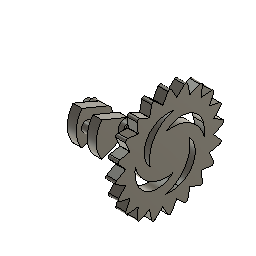
shaft (Autodesk Fusion 360 design; units mm, degrees)
part number: 2026-03-27-15-48-30-231
Autodesk Fusion 360 part; units mm, degrees
sketch "Sketch1" plane through (0, 0, 0) normal (1, 0, 0) x (0, 1, 0)
  circle A0 centre (0, 0) radius 2.5 construction
  circle A1 centre (0, 0) radius 14.5
  circle A2 centre (0, 0) radius 9.5 construction
  circle A3 centre (-9.4991, -0.128) radius 2.5
  circle A4 centre (0, 0) radius 3.5
  line L0 (1.3394, 3.2336) -> (-11.6607, 8.6184)
  line L1 (1.3394, -3.2336) -> (-11.6607, -8.6184)
  line L2 (0, 0) -> (-7.0024, 0) construction
  dimension "d1" = 29
  dimension "d2" = 5
  dimension "d3" = 5
  dimension "d4" = 5
  dimension "d5" = 7
  dimension "d6" = 45
  dimension "d7" = 22.5
  constraint coincident A0.centre A1.centre
  constraint coincident A2 A3.centre
  constraint concentric A2 A4
  constraint coincident A4 L0.start
  constraint coincident A1 L0.end
  constraint coincident A4 L1.start
  constraint coincident A1 L1.end
  constraint tangent A4 L0
  constraint tangent A4 L1
  constraint coincident A3 L2.end
  constraint horizontal L2
  measures "d1" diameter of A1
  measures "d2" diameter of A0
  measures "d3" distance of A1 A2
  measures "d4" diameter of A3
  measures "d5" diameter of A4
  measures "d6" angle of L0 L1
  measures "d7" angle of L1 L2
extrude "Extrude1" add sketch "Sketch1" along normal blind 4.5 contours A1 A4 L0 L1 | A4 picked at (-7.3196, 4.4977)
sketch "Sketch2" plane through (0, 0, 0) normal (-1, 0, 0) x (0, -1, 0)
  circle A0 centre (9.4991, -0.128) radius 2.5
  line L0 (11.6607, 8.6184) -> (-1.3394, 3.2336)
  arc A1 (-1.3394, 3.2336) -> (-1.3394, -3.2336) centre (0, 0) ccw
  line L1 (-1.3394, -3.2336) -> (11.6607, -8.6184)
  arc A2 (11.6607, -8.6184) -> (11.6607, 8.6184) centre (0, 0) ccw
extrude "Extrude2" add sketch "Sketch2" against normal blind 10 contours A0
sketch "Sketch3" plane through (10, 0, 0) normal (1, 0, 0) x (0, 1, 0)
  circle A0 centre (-9.4991, -0.128) radius 2.5
  line L0 (1.3394, 3.2336) -> (-11.6607, 8.6184)
  circle A1 centre (-9.4991, -0.128) radius 2.5
  line L1 (1.3394, 3.2336) -> (-11.6607, 8.6184)
  arc A2 (-11.6607, 8.6184) -> (-11.6607, -8.6184) centre (0, 0) ccw
  line L2 (-11.6607, -8.6184) -> (1.3394, -3.2336)
  arc A3 (1.3394, -3.2336) -> (1.3394, 3.2336) centre (0, 0) ccw
extrude "Extrude3" add sketch "Sketch3" along normal blind 4.5 contours A0 A1 | L0 L1 A2 L2 A3
sketch "Sketch4" plane through (14.5, 0, 0) normal (1, 0, 0) x (0, 1, 0)
  arc A0 (1.3394, -3.2336) -> (1.3394, 3.2336) centre (0, 0) ccw
  line L0 (1.3394, 3.2336) -> (-11.6607, 8.6184)
  arc A1 (-11.6607, 8.6184) -> (-11.6607, -8.6184) centre (0, 0) ccw
  line L1 (-11.6607, -8.6184) -> (1.3394, -3.2336)
  circle A2 centre (0, 0) radius 3.5
  dimension "d14" = 7
  constraint coincident A0.centre A1.centre
  measures "d14" diameter of A2
extrude "Extrude4" add sketch "Sketch4" along normal blind 2.5 contours A0 A2
sketch "Sketch5" plane through (17, 0, 0) normal (1, 0, 0) x (0, 1, 0)
  circle A0 centre (0, 0) radius 3.5
  circle A1 centre (0, 0) radius 2.5
  dimension "d17" = 5
  constraint concentric A0 A1
  measures "d17" diameter of A1
extrude "Extrude5" add sketch "Sketch5" along normal blind 15 contours A1
sketch "Sketch6" plane through (0, 0, 0) normal (-1, 0, 0) x (0, -1, 0)
  line L0 (11.6607, 8.6184) -> (-1.3394, 3.2336)
  arc A0 (-1.3394, 3.2336) -> (-1.3394, -3.2336) centre (0, 0) ccw
  line L1 (-1.3394, -3.2336) -> (11.6607, -8.6184)
  arc A1 (11.6607, -8.6184) -> (11.6607, 8.6184) centre (0, 0) ccw
  circle A2 centre (0, 0) radius 3.5
  constraint coincident A0.centre A1.centre
extrude "Extrude6" add sketch "Sketch6" along normal blind 2.5 contours A0 A2
sketch "Sketch7" plane through (-2.5, 0, 0) normal (-1, 0, 0) x (0, -1, 0)
  circle A0 centre (0, 0) radius 3.5
  circle A1 centre (0, 0) radius 2.5
  dimension "d22" = 5
  constraint concentric A0 A1
  measures "d22" diameter of A1
extrude "Extrude7" add sketch "Sketch7" along normal blind 2.5 contours A1
sketch "Sketch8" plane through (32, 0, 0) normal (1, 0, 0) x (0, 1, 0)
  circle A0 centre (0, 0) radius 2.5
  circle A1 centre (0, 0) radius 2.5
  circle A2 centre (0, 0) radius 22.5
  dimension "d25" = 20
  dimension "d26" = 5
  constraint concentric A0 A1
  constraint concentric A1 A2
  measures "d25" distance of A1 A2
  measures "d26" diameter of A1
extrude "Extrude8" add sketch "Sketch8" along normal blind 5 contours A0 A1 | A2
sketch "Sketch9" plane through (37, 0, 0) normal (1, 0, 0) x (0, 1, 0)
  circle A0 centre (0, 0) radius 22.5
  line L0 (-3.4641, -22.2317) -> (0, -28.2317)
  line L1 (0, -28.2317) -> (3.4641, -22.2317)
  line L2 (3.4641, -22.2317) -> (-3.4641, -22.2317)
  point P0 (0, -24.2317)
  dimension "d29" = 2
  constraint coincident A0 L1.end
  constraint horizontal L2
  constraint coincident A0 L0.start
  measures "d29" distance of P0 L2
extrude "Extrude9" add sketch "Sketch9" against normal up to surface (5 mm away) contours A0 L0 L1
fillet "Fillet1" radius 1 1 edges at (34.5, 0, -28.2317)
pattern_circular "C-Pattern2" count 20 over 360 about axis through (1.75, 0, 0) along (1, 0, 0) of "Extrude9", "Fillet1"
sketch "Sketch10" plane through (37, 0, 0) normal (1, 0, 0) x (0, 1, 0)
  arc A0 (-9.0842, -25.1558) -> (-7.4369, -25.691) centre (-8.1061, -24.9479) ccw
  line L0 (-7.4369, -25.691) -> (-3.5754, -22.2141)
  arc A1 (-3.5754, -22.2141) -> (-3.4641, -22.2317) centre (0, 0) ccw
  line L1 (-3.4641, -22.2317) -> (-0.866, -26.7317)
  arc A2 (-0.866, -26.7317) -> (0.866, -26.7317) centre (0, -26.2317) ccw
  line L2 (0.866, -26.7317) -> (3.4641, -22.2317)
  arc A3 (3.4641, -22.2317) -> (3.5754, -22.2141) centre (0, 0) ccw
  line L3 (3.5754, -22.2141) -> (7.4369, -25.691)
  arc A4 (7.4369, -25.691) -> (9.0842, -25.1558) centre (8.1061, -24.9479) ccw
  line L4 (9.0842, -25.1558) -> (10.1645, -20.0732)
  arc A5 (10.1645, -20.0732) -> (10.265, -20.022) centre (0, 0) ccw
  line L5 (10.265, -20.022) -> (15.0119, -22.1355)
  arc A6 (15.0119, -22.1355) -> (16.4131, -21.1174) centre (15.4186, -21.2219) ccw
  line L6 (16.4131, -21.1174) -> (15.87, -15.9497)
  arc A7 (15.87, -15.9497) -> (15.9497, -15.87) centre (0, 0) ccw
  line L7 (15.9497, -15.87) -> (21.1174, -16.4131)
  arc A8 (21.1174, -16.4131) -> (22.1355, -15.0119) centre (21.2219, -15.4186) ccw
  line L8 (22.1355, -15.0119) -> (20.022, -10.265)
  arc A9 (20.022, -10.265) -> (20.0732, -10.1645) centre (0, 0) ccw
  line L9 (20.0732, -10.1645) -> (25.1558, -9.0842)
  arc A10 (25.1558, -9.0842) -> (25.691, -7.4369) centre (24.9479, -8.1061) ccw
  line L10 (25.691, -7.4369) -> (22.2141, -3.5754)
  arc A11 (22.2141, -3.5754) -> (22.2317, -3.4641) centre (0, 0) ccw
  line L11 (22.2317, -3.4641) -> (26.7317, -0.866)
  arc A12 (26.7317, -0.866) -> (26.7317, 0.866) centre (26.2317, 0) ccw
  line L12 (26.7317, 0.866) -> (22.2317, 3.4641)
  arc A13 (22.2317, 3.4641) -> (22.2141, 3.5754) centre (0, 0) ccw
  line L13 (22.2141, 3.5754) -> (25.691, 7.4369)
  arc A14 (25.691, 7.4369) -> (25.1558, 9.0842) centre (24.9479, 8.1061) ccw
  line L14 (25.1558, 9.0842) -> (20.0732, 10.1645)
  arc A15 (20.0732, 10.1645) -> (20.022, 10.265) centre (0, 0) ccw
  line L15 (20.022, 10.265) -> (22.1355, 15.0119)
  arc A16 (22.1355, 15.0119) -> (21.1174, 16.4131) centre (21.2219, 15.4186) ccw
  line L16 (21.1174, 16.4131) -> (15.9497, 15.87)
  arc A17 (15.9497, 15.87) -> (15.87, 15.9497) centre (0, 0) ccw
  line L17 (15.87, 15.9497) -> (16.4131, 21.1174)
  arc A18 (16.4131, 21.1174) -> (15.0119, 22.1355) centre (15.4186, 21.2219) ccw
  line L18 (15.0119, 22.1355) -> (10.265, 20.022)
  arc A19 (10.265, 20.022) -> (10.1645, 20.0732) centre (0, 0) ccw
  line L19 (10.1645, 20.0732) -> (9.0842, 25.1558)
  arc A20 (9.0842, 25.1558) -> (7.4369, 25.691) centre (8.1061, 24.9479) ccw
  line L20 (7.4369, 25.691) -> (3.5754, 22.2141)
  arc A21 (3.5754, 22.2141) -> (3.4641, 22.2317) centre (0, 0) ccw
  line L21 (3.4641, 22.2317) -> (0.866, 26.7317)
  arc A22 (0.866, 26.7317) -> (-0.866, 26.7317) centre (0, 26.2317) ccw
  line L22 (-0.866, 26.7317) -> (-3.4641, 22.2317)
  arc A23 (-3.4641, 22.2317) -> (-3.5754, 22.2141) centre (0, 0) ccw
  line L23 (-3.5754, 22.2141) -> (-7.4369, 25.691)
  arc A24 (-7.4369, 25.691) -> (-9.0842, 25.1558) centre (-8.1061, 24.9479) ccw
  line L24 (-9.0842, 25.1558) -> (-10.1645, 20.0732)
  arc A25 (-10.1645, 20.0732) -> (-10.265, 20.022) centre (0, 0) ccw
  line L25 (-10.265, 20.022) -> (-15.0119, 22.1355)
  arc A26 (-15.0119, 22.1355) -> (-16.4131, 21.1174) centre (-15.4186, 21.2219) ccw
  line L26 (-16.4131, 21.1174) -> (-15.87, 15.9497)
  arc A27 (-15.87, 15.9497) -> (-15.9497, 15.87) centre (0, 0) ccw
  line L27 (-15.9497, 15.87) -> (-21.1174, 16.4131)
  arc A28 (-21.1174, 16.4131) -> (-22.1355, 15.0119) centre (-21.2219, 15.4186) ccw
  line L28 (-22.1355, 15.0119) -> (-20.022, 10.265)
  arc A29 (-20.022, 10.265) -> (-20.0732, 10.1645) centre (0, 0) ccw
  line L29 (-20.0732, 10.1645) -> (-25.1558, 9.0842)
  arc A30 (-25.1558, 9.0842) -> (-25.691, 7.4369) centre (-24.9479, 8.1061) ccw
  line L30 (-25.691, 7.4369) -> (-22.2141, 3.5754)
  arc A31 (-22.2141, 3.5754) -> (-22.2317, 3.4641) centre (0, 0) ccw
  line L31 (-22.2317, 3.4641) -> (-26.7317, 0.866)
  arc A32 (-26.7317, 0.866) -> (-26.7317, -0.866) centre (-26.2317, 0) ccw
  line L32 (-26.7317, -0.866) -> (-22.2317, -3.4641)
  arc A33 (-22.2317, -3.4641) -> (-22.2141, -3.5754) centre (0, 0) ccw
  line L33 (-22.2141, -3.5754) -> (-25.691, -7.4369)
  arc A34 (-25.691, -7.4369) -> (-25.1558, -9.0842) centre (-24.9479, -8.1061) ccw
  line L34 (-25.1558, -9.0842) -> (-20.0732, -10.1645)
  arc A35 (-20.0732, -10.1645) -> (-20.022, -10.265) centre (0, 0) ccw
  line L35 (-20.022, -10.265) -> (-22.1355, -15.0119)
  arc A36 (-22.1355, -15.0119) -> (-21.1174, -16.4131) centre (-21.2219, -15.4186) ccw
  line L36 (-21.1174, -16.4131) -> (-15.9497, -15.87)
  arc A37 (-15.9497, -15.87) -> (-15.87, -15.9497) centre (0, 0) ccw
  line L37 (-15.87, -15.9497) -> (-16.4131, -21.1174)
  arc A38 (-16.4131, -21.1174) -> (-15.0119, -22.1355) centre (-15.4186, -21.2219) ccw
  line L38 (-15.0119, -22.1355) -> (-10.265, -20.022)
  arc A39 (-10.265, -20.022) -> (-10.1645, -20.0732) centre (0, 0) ccw
  line L39 (-10.1645, -20.0732) -> (-9.0842, -25.1558)
  circle A40 centre (0, 0) radius 5
  circle A41 centre (0, 0) radius 17.5
  arc A42 (16.9354, 4.4092) -> (-4.8387, -1.2598) centre (6.0484, 1.5747) ccw
  arc A43 (2.1966, 17.3616) -> (-9.6774, -2.5195) centre (6.0484, 1.5747) ccw
  arc A44 (-4.4092, 16.9354) -> (1.2598, -4.8387) centre (-1.5747, 6.0484) ccw
  arc A45 (-17.3616, 2.1966) -> (2.5195, -9.6774) centre (-1.5747, 6.0484) ccw
  arc A46 (-16.9354, -4.4092) -> (4.8387, 1.2598) centre (-6.0484, -1.5747) ccw
  arc A47 (-2.1966, -17.3616) -> (9.6774, 2.5195) centre (-6.0484, -1.5747) ccw
  arc A48 (4.4092, -16.9354) -> (-1.2598, 4.8387) centre (1.5747, -6.0484) ccw
  arc A49 (17.3616, -2.1966) -> (-2.5195, 9.6774) centre (1.5747, -6.0484) ccw
  dimension "d38" = 35
  dimension "d39" = 10
  dimension "d42" = 360
  constraint concentric A1 A40
  constraint concentric A40 A41
  constraint tangent A41 A42
  constraint tangent A40 A42
  constraint coincident A40 A42.end
  constraint coincident A41 A42.start
  constraint concentric A42 A43
  constraint coincident A41 A43.start
  measures "d38" diameter of A41
  measures "d39" diameter of A40
extrude "Extrude10" cut sketch "Sketch10" against normal blind 8 contours A41 A45 A46 | A41 A43 A44 | A41 A47 A48 | A41 A42 A49
